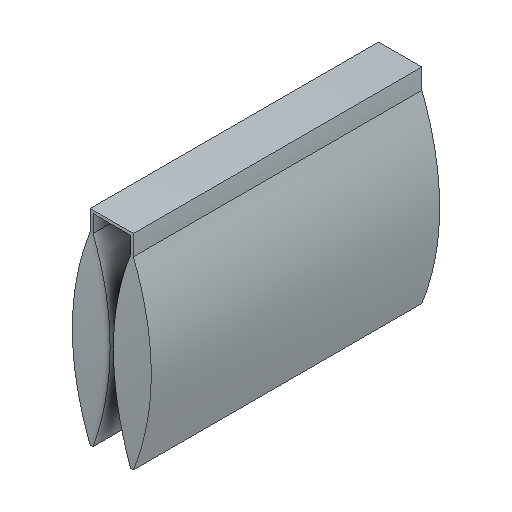
# Autodesk Inventor part: COTS_PROFOTO_Tripod_Sandbag
Saved by Autodesk Inventor 2027 (Build 310192060, 192F)
## iProperties
Created: 2025-05-09
Part Number: COTS_PROFOTO_Tripod_Sandbag
Material: Generic
Document SubType Name: Modeling
Designer: User
Density: 1 g/cm^3
Appearance: Zinc
Author: User
Autodesk Inventor part; units mm, degrees
ref_plane "YZ Plane" through (0, 0, 0) normal (1, 0, 0) x (0, 1, 0)
ref_plane "XZ Plane" through (0, 0, 0) normal (0, 1, 0) x (-1, 0, 0)
ref_plane "XY Plane" through (0, 0, 0) normal (0, 0, 1) x (1, 0, 0)
sketch "Sketch1" plane through (0, 0, 0) normal (0, 0, 1) x (1, 0, 0)
  line L0 (-15, 0) -> (15, 0)
  line L1 (-15, -2) -> (15, -2)
  line L2 (15, -2) -> (15, 0)
  line L3 (-15, -2) -> (-15, 0)
  line L4 (-15, -2) -> (-15, -14)
  line L5 (-15, -14) -> (-13, -14)
  line L6 (-13, -14) -> (-13, -2)
  line L7 (15, -2) -> (15, -14)
  line L8 (15, -14) -> (13, -14)
  line L9 (13, -14) -> (13, -2)
  line L10 (-15, -14) -> (-39.6756, -78.3934) construction
  line L11 (-39.6756, -78.3934) -> (-15, -142) construction
  spline S0 degree 2 poles (-15, -14) (-39.6756, -78.3934) (-15, -142) knots 1 1 1 2 2 2
  line L12 (-13, -14) -> (10.6432, -74.6661) construction
  line L13 (10.6432, -74.6661) -> (-13, -142) construction
  spline S1 degree 2 poles (-13, -14) (10.6432, -74.6661) (-13, -142) knots 1 1 1 2 2 2
  line L14 (-15, -142) -> (-13, -142)
  line L15 (0, -7.2166) -> (0, 3.7875)
  line L16 (15, -14) -> (39.6756, -78.3934) construction
  line L17 (39.6756, -78.3934) -> (15, -142) construction
  spline S2 degree 2 poles (15, -14) (39.6756, -78.3934) (15, -142) knots 1 1 1 2 2 2
  line L18 (13, -14) -> (-10.6432, -74.6661) construction
  line L19 (-10.6432, -74.6661) -> (13, -142) construction
  spline S3 degree 2 poles (13, -14) (-10.6432, -74.6661) (13, -142) knots 1 1 1 2 2 2
  line L20 (15, -142) -> (13, -142)
  point P0 (0, 0)
  dimension "d0" = 30
  dimension "d1" = 15
  dimension "d2" = 2
  dimension "d3" = 2
  dimension "d4" = 2
  dimension "d5" = 140
  dimension "d8" = 14
  constraints: 26 end point, 4 perpendicular, 4 point on line, 4 symmetric about line, 3 horizontal, 2 parallel, 2 vertical, 12 other
  measures "d0" distance of L0.start L0.end
  measures "d1" distance of point (0, 0) L0.start
  measures "d2" distance of L4.end L5.end
  measures "d3" distance of L7.end L8.end
  measures "d4" distance between parallel lines of L1 L0
  measures "d5" distance from line of L1 L11.end
  measures "d8" distance between parallel lines of L5 L0
extrude "Extrusion1" add sketch "Sketch1" along normal blind 200
equation "\"d1\" = 0.5 * d0"
body "Solid1"
